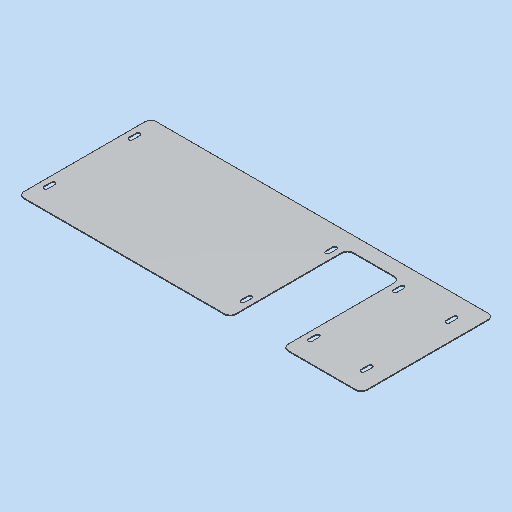
# Autodesk Inventor part: SE0004AN000_G01_107
Saved by Autodesk Inventor 2023.3 (Build 273359000, 359)
## iProperties
RuleStatus: InUse
Created: 2021-07-09
Part Number: SE0004AN000_G01_107
Material: 3.3535 AlMg3 - AW 5754 (Blech)
Description: =<RBPARTNOTITLE2>
Document SubType Name: Blech
Designer: frt9bw
Mass: 1578.92 g
Surface Area: 5925.97 cm^2
Volume: 585.003 cm^3
Density: 2.699 g/cm^3
Sheet Metal Rule: Standard_mm
Appearance: Aluminium AnP
Vendor: ASW
AnP_Kategorie: 1
AnP_Material: =<Material>
MaxAbmaße: 2 x 363 x 941 (FM)
AnP_TemplVers: 20200821
RBDOCUMENTTYPE: DRF
RBDOCUMENTVERSION: 00
RBDRAWINGMAINSCALE: 1:1
RBDRAWINGMISSINGSPEC: --
RBDRAWINGVOLUME: --
RBDSV1: 0850
RBGBEDGESIN1: +0,5
RBGBEDGESIN2: +0,2
RBGBEDGESOUT1: -0,3
RBGBEDGESOUT2: -0,1
RBMATERIAL: =<Material>
RBMATMEETS: --
RBMATNO: =<Part Number>
RBPARTMADEOF: 2 x 363 x 941 (FM)
RBPARTNO: SIEHE MNR
RBPARTNOTITLE1: manufactured part
RBPARTNOTITLE2: Anfertigungsteil
RBPARTSAFETYINDICATOR: --
RBSURFACE: --
RBSURFACE2: eloxiert E6/EV1 aluminiumfarbig
RBZEDGESNORM: ISO13715:2002-06
RBZGENDIMCLASS: m
RBZGENDIMNORM: ISO 2768-1:1989-11
RBZGENGEOCLASS: H
RBZGENGEONORM: ISO 2768-2:1989-11
RBZSURFACENORM: ISO13D2:2002-02
RBZTOLERANCENORM: ISO 14405-1:2010-12
Author: frt9bw
Keywords: =<RBPARTMADEOF>
Comments: =<RBSURFACE2>
Revision Number: 01
Autodesk Inventor part; units mm, degrees
ref_plane "YZ Plane" through (0, 0, 0) normal (1, 0, 0) x (0, 1, 0)
ref_plane "XZ Plane" through (0, 0, 0) normal (0, 1, 0) x (-1, 0, 0)
ref_plane "XY Plane" through (0, 0, 0) normal (0, 0, 1) x (1, 0, 0)
sketch "Skizze1" plane through (0, 0, 0) normal (0, 0, 1) x (1, 0, 0)
  line L0 (0, 0) -> (941, 0)
  line L1 (941, 0) -> (941, 363)
  line L2 (941, 363) -> (0, 363)
  line L3 (0, 363) -> (0, 0)
  dimension "d0" = 941
  dimension "d1" = 363
  measures "d0" distance of L2.end L1.end
  measures "d1" distance from line of L0.start L2
extrude "Grobblech1" add sketch "Skizze1" along normal blind 2
sketch "Skizze2" plane through (0, 0, 2) normal (0, 0, 1) x (1, 0, 0)
  line L0 (0, 0) -> (0, 363) projected
  line L1 (941, 0) -> (0, 0) projected
  line L2 (941, 363) -> (941, 0) projected
  line L3 (0, 363) -> (941, 363) projected
  line L4 (725, 0) -> (581, 0)
  line L5 (581, 0) -> (581, 322)
  line L6 (581, 322) -> (725, 322)
  line L7 (725, 322) -> (725, 0)
  dimension "d3" = 144
  dimension "d4" = 216
  dimension "d5" = 41
  constraints: 8 end point, 2 parallel, 1 horizontal, 1 perpendicular, 1 point on line
  measures "d3" distance between parallel lines of L7 L5
  measures "d4" distance between parallel lines of L2 L7
  measures "d5" distance between parallel lines of L6 L3
extrude "Extrusion1" cut sketch "Skizze2" against normal blind 10 contours L5 L6 L7 L1
sketch "Skizze3" plane through (0, 0, 2) normal (0, 0, 1) x (1, 0, 0)
  line L0 (581, 0) -> (581, 322) projected
  line L1 (581, 322) -> (725, 322) projected
  line L2 (725, 322) -> (725, 0) projected
  line L3 (941, 0) -> (725, 0) projected
  line L4 (941, 363) -> (941, 0) projected
  line L5 (0, 363) -> (941, 363) projected
  line L6 (0, 0) -> (0, 363) projected
  line L7 (581, 0) -> (0, 0) projected
  line L8 (20.5, 308) -> (20.5, 288) construction
  line L9 (15, 308) -> (15, 288)
  line L10 (26, 288) -> (26, 308)
  arc A0 (26, 308) -> (15, 308) centre (20.5, 308) ccw
  arc A1 (15, 288) -> (26, 288) centre (20.5, 288) ccw
  line L11 (20.5, 55) -> (20.5, 75) construction
  line L12 (26, 55) -> (26, 75)
  line L13 (15, 75) -> (15, 55)
  arc A2 (15, 55) -> (26, 55) centre (20.5, 55) ccw
  arc A3 (26, 75) -> (15, 75) centre (20.5, 75) ccw
  line L14 (560.5, 308) -> (560.5, 288) construction
  line L15 (555, 308) -> (555, 288)
  line L16 (566, 288) -> (566, 308)
  arc A4 (566, 308) -> (555, 308) centre (560.5, 308) ccw
  arc A5 (555, 288) -> (566, 288) centre (560.5, 288) ccw
  line L17 (560.5, 55) -> (560.5, 75) construction
  line L18 (566, 55) -> (566, 75)
  line L19 (555, 75) -> (555, 55)
  arc A6 (555, 55) -> (566, 55) centre (560.5, 55) ccw
  arc A7 (566, 75) -> (555, 75) centre (560.5, 75) ccw
  line L20 (745.5, 308) -> (745.5, 288) construction
  line L21 (740, 308) -> (740, 288)
  line L22 (751, 288) -> (751, 308)
  arc A8 (751, 308) -> (740, 308) centre (745.5, 308) ccw
  arc A9 (740, 288) -> (751, 288) centre (745.5, 288) ccw
  line L23 (745.5, 55) -> (745.5, 80.5) construction
  line L24 (890.5, 55) -> (890.5, 75) construction
  line L25 (896, 55) -> (896, 75)
  line L26 (885, 75) -> (885, 55)
  arc A10 (885, 55) -> (896, 55) centre (890.5, 55) ccw
  arc A11 (896, 75) -> (885, 75) centre (890.5, 75) ccw
  line L27 (890.5, 308) -> (890.5, 288) construction
  line L28 (885, 308) -> (885, 288)
  line L29 (896, 288) -> (896, 308)
  arc A12 (896, 308) -> (885, 308) centre (890.5, 308) ccw
  arc A13 (885, 288) -> (896, 288) centre (890.5, 288) ccw
  line L30 (745.5, 55) -> (745.5, 75) construction
  line L31 (751, 55) -> (751, 75)
  line L32 (740, 75) -> (740, 55)
  arc A14 (740, 55) -> (751, 55) centre (745.5, 55) ccw
  arc A15 (751, 75) -> (740, 75) centre (745.5, 75) ccw
  point P0 (20.5, 298)
  point P1 (20.5, 65)
  point P2 (560.5, 298)
  point P3 (560.5, 65)
  point P4 (745.5, 298)
  point P5 (745.5, 67.75)
  point P6 (890.5, 65)
  point P7 (890.5, 298)
  point P8 (745.5, 65)
  dimension "d8" = 55
  dimension "d9" = 55
  dimension "d10" = 20.5
  dimension "d11" = 50.5
  dimension "d12" = 185
  dimension "d13" = 540
  dimension "d14" = 11
  dimension "d15" = 20
  dimension "d16" = 11
  dimension "d17" = 20
  dimension "d18" = 11
  dimension "d19" = 20
  dimension "d20" = 11
  dimension "d21" = 20
  dimension "d22" = 11
  dimension "d24" = 11
  dimension "d25" = 11
  dimension "d26" = 20
  dimension "d27" = 20
  dimension "d28" = 20
  dimension "d29" = 25.5
  dimension "d30" = 20
  dimension "d31" = 11
  constraints: 68 end point, 32 point on circle, 32 tangent, 16 centre point, 10 parallel, 9 midpoint, 7 horizontal alignment, 4 point on line, 4 vertical alignment, 2 vertical
  measures "d8" distance from line of L8.start L5
  measures "d9" distance from line of L11.start L7
  measures "d10" distance from line of L11.start L6
  measures "d11" distance from line of L4 L24.start
  measures "d12" distance of L20.start L14.start
  measures "d13" distance of L14.start L8.start
  measures "d14" diameter of A1
  measures "d15" distance of L11.start L11.end
  measures "d16" diameter of A3
  measures "d17" distance of L14.start L14.end
  measures "d18" diameter of A5
  measures "d19" distance of L17.start L17.end
  measures "d20" diameter of A7
  measures "d21" distance of L20.start L20.end
  measures "d22" diameter of A9
  measures "d24" diameter of A11
  measures "d25" diameter of A13
  measures "d26" distance of L8.start L8.end
  measures "d27" distance of L27.end L27.start
  measures "d28" distance of L24.end L24.start
  measures "d29" distance of L23.start L23.end
  measures "d30" distance of L23.start L30.end
  measures "d31" diameter of A15
extrude "Extrusion2" cut sketch "Skizze3" against normal through all contours A0 L10 A1 L9 | A2 L13 A3 L12 | A4 L16 A5 L15 | A6 L19 A7 L18 | A8 L22 A9 L21 | A10 L26 A11 L25 | A12 L29 A13 L28 | A14 L32 A15 L31
fillet "Rundung1" radius 15 8 edges at (0, 0, 1) (0, 363, 1) (581, 322, 1) (581, 0, 1) (725, 0, 1) (941, 0, 1) (941, 363, 1) (725, 322, 1)
equation "\"d2\" = Stärke"
equation "\"Biegeradius\" = Stärke"
equation "\"BreiteBiegungsfreistellung\" = Stärke"
equation "\"TiefeBiegungsfreistellung\" = 0.5 * Stärke"
equation "\"GrößeEckenfreistellung\" = 4 * Stärke"
equation "\"MinimalRest\" = 2 * Stärke"
equation "\"Übergangsradius\" = Biegeradius"
equation "\"JacobiRadiusGröße\" = Biegeradius"
equation "\"Abstandsgröße\" = Stärke"
equation "\"Stärke\" = 2"
